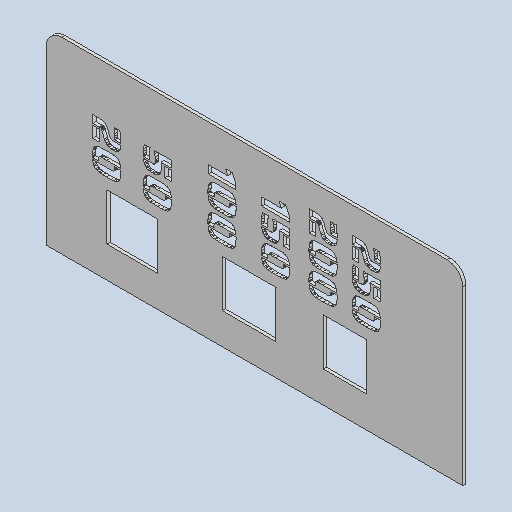
# Autodesk Inventor part: GBK-RK-0052 Cipolletti L
Saved by Autodesk Inventor 2026.2 (Build 302298000, 298)
## iProperties
Created: 2026-10-23
Part Number: GBK-RK-0052 Cipolletti L
Material: Generic
Description: Шкала расхода водослива, левая (трафарет, Saira Stencil)
Document SubType Name: Sheet Metal
Designer: admin
Density: 1 g/cm^3
Sheet Metal Rule: Default_mm
Appearance: Default
Flat Pattern Width: 12 cm
Flat Pattern Length: 26.6044 cm
Flat Pattern Area: 319.253 cm^2
Sheet Metal Width: 120,000 mm
Sheet Metal Length: 266,044 mm
Sheet Metal Area: 31925,333 mm^2
Author: admin
Autodesk Inventor part; units mm, degrees
(part 1 of 2)
ref_plane "YZ Plane" through (0, 0, 0) normal (1, 0, 0) x (0, 1, 0)
ref_plane "XZ Plane" through (0, 0, 0) normal (0, 1, 0) x (-1, 0, 0)
ref_plane "XY Plane" through (0, 0, 0) normal (0, 0, 1) x (1, 0, 0)
sketch "Sketch1" plane through (0, 0, 0) normal (0, 0, 1) x (1, 0, 0)
  line L0 (0, 0) -> (266.0444, 0)
  line L1 (266.0444, 0) -> (266.0444, 120)
  line L2 (266.0444, 120) -> (0, 120)
  line L3 (0, 120) -> (0, 0)
extrude "Plate1" add sketch "Sketch1" along normal blind 2
sketch "Sketch3" plane through (0, 0, 0) normal (0, 0, -1) x (-1, 0, 0)
  line L0 (-38.8424, 20) -> (-71.2409, 20)
  line L1 (-71.2409, 20) -> (-71.2409, 50)
  line L2 (-71.2409, 50) -> (-38.8424, 50)
  line L3 (-38.8424, 50) -> (-38.8424, 20)
  line L4 (-112.4742, 20) -> (-146.7233, 20)
  line L5 (-146.7233, 20) -> (-146.7233, 50)
  line L6 (-146.7233, 50) -> (-112.4742, 50)
  line L7 (-112.4742, 50) -> (-112.4742, 20)
  line L8 (-177.0426, 20) -> (-204.7056, 20)
  line L9 (-204.7056, 20) -> (-204.7056, 50)
  line L10 (-204.7056, 50) -> (-177.0426, 50)
  line L11 (-177.0426, 50) -> (-177.0426, 20)
  line L12 (-46.9971, 86.8148) -> (-47.3068, 85.1782)
  line L13 (-47.3068, 85.1782) -> (-47.6264, 81.8282)
  line L14 (-47.6264, 81.8282) -> (-47.6363, 80.1152)
  line L15 (-47.6363, 80.1152) -> (-43.6492, 80.1152)
  line L16 (-43.6492, 80.1152) -> (-43.7063, 80.8612)
  line L17 (-43.7063, 80.8612) -> (-43.7252, 82.1328)
  line L18 (-43.7252, 82.1328) -> (-43.6743, 83.5339)
  line L19 (-43.6743, 83.5339) -> (-43.5214, 85.2288)
  line L20 (-43.5214, 85.2288) -> (-43.3176, 86.8148)
  line L21 (-43.3176, 86.8148) -> (-46.9971, 86.8148)
  line L22 (-32.4233, 87.1705) -> (-33.9254, 87.1454)
  line L23 (-33.9254, 87.1454) -> (-35.1079, 87.0705)
  line L24 (-35.1079, 87.0705) -> (-35.6017, 87.0043)
  line L25 (-35.6017, 87.0043) -> (-36.4848, 86.7867)
  line L26 (-36.4848, 86.7867) -> (-36.8737, 86.6351)
  line L27 (-36.8737, 86.6351) -> (-37.2557, 86.4372)
  line L28 (-37.2557, 86.4372) -> (-37.9388, 85.9317)
  line L29 (-37.9388, 85.9317) -> (-38.24, 85.6243)
  line L30 (-38.24, 85.6243) -> (-38.5205, 85.2689)
  line L31 (-38.5205, 85.2689) -> (-39.0401, 84.3802)
  line L32 (-39.0401, 84.3802) -> (-39.2786, 83.8466)
  line L33 (-39.2786, 83.8466) -> (-40.4773, 80.8543)
  line L34 (-40.4773, 80.8543) -> (-40.6989, 80.333)
  line L35 (-40.6989, 80.333) -> (-40.9007, 79.8874)
  line L36 (-40.9007, 79.8874) -> (-41.0894, 79.5399)
  line L37 (-41.0894, 79.5399) -> (-41.2722, 79.3203)
  line L38 (-41.2722, 79.3203) -> (-41.467, 79.1753)
  line L39 (-41.467, 79.1753) -> (-41.6917, 79.0924)
  line L40 (-41.6917, 79.0924) -> (-41.9894, 79.0536)
  line L41 (-41.9894, 79.0536) -> (-42.3949, 79.0405)
  line L42 (-42.3949, 79.0405) -> (-47.6123, 79.0405)
  line L43 (-47.6123, 79.0405) -> (-47.5003, 77.8999)
  line L44 (-47.5003, 77.8999) -> (-47.3167, 76.9312)
  line L45 (-47.3167, 76.9312) -> (-47.1917, 76.5049)
  line L46 (-47.1917, 76.5049) -> (-46.8401, 75.7438)
  line L47 (-46.8401, 75.7438) -> (-46.6136, 75.4091)
  line L48 (-46.6136, 75.4091) -> (-46.2996, 75.0616)
  line L49 (-46.2996, 75.0616) -> (-45.5137, 74.5058)
  line L50 (-45.5137, 74.5058) -> (-44.5168, 74.1353)
  line L51 (-44.5168, 74.1353) -> (-43.3092, 73.9502)
  line L52 (-43.3092, 73.9502) -> (-42.6265, 73.9269)
  line L53 (-42.6265, 73.9269) -> (-41.4782, 73.978)
  line L54 (-41.4782, 73.978) -> (-40.0487, 74.2468)
  line L55 (-40.0487, 74.2468) -> (-39.2911, 74.5538)
  line L56 (-39.2911, 74.5538) -> (-38.971, 74.7459)
  line L57 (-38.971, 74.7459) -> (-38.6913, 74.9527)
  line L58 (-38.6913, 74.9527) -> (-38.1799, 75.4577)
  line L59 (-38.1799, 75.4577) -> (-37.5328, 76.4426)
  line L60 (-37.5328, 76.4426) -> (-37.1813, 77.2508)
  line L61 (-37.1813, 77.2508) -> (-35.775, 80.8822)
  line L62 (-35.775, 80.8822) -> (-35.6011, 81.3008)
  line L63 (-35.6011, 81.3008) -> (-35.4396, 81.6372)
  line L64 (-35.4396, 81.6372) -> (-35.2877, 81.8881)
  line L65 (-35.2877, 81.8881) -> (-35.1358, 82.0568)
  line L66 (-35.1358, 82.0568) -> (-34.955, 82.1596)
  line L67 (-34.955, 82.1596) -> (-34.7244, 82.2125)
  line L68 (-34.7244, 82.2125) -> (-34.3859, 82.2307)
  line L69 (-34.3859, 82.2307) -> (-33.8814, 82.2366)
  line L70 (-33.8814, 82.2366) -> (-29.8424, 82.2366)
  line L71 (-29.8424, 82.2366) -> (-29.8424, 87.1705)
  line L72 (-29.8424, 87.1705) -> (-32.4233, 87.1705)
  line L73 (-33.8295, 81.1619) -> (-33.8295, 73.9269)
  line L74 (-33.8295, 73.9269) -> (-29.8424, 73.9269)
  line L75 (-29.8424, 73.9269) -> (-29.8424, 81.1619)
  line L76 (-29.8424, 81.1619) -> (-33.8295, 81.1619)
  line L77 (-38.6394, 62.2136) -> (-40.4783, 62.2205)
  line L78 (-40.4783, 62.2205) -> (-41.5519, 62.2415)
  line L79 (-41.5519, 62.2415) -> (-42.4667, 62.3184)
  line L80 (-42.4667, 62.3184) -> (-43.0619, 62.4453)
  line L81 (-43.0619, 62.4453) -> (-43.2596, 62.547)
  line L82 (-43.2596, 62.547) -> (-43.5332, 62.8226)
  line L83 (-43.5332, 62.8226) -> (-43.6094, 62.9965)
  line L84 (-43.6094, 62.9965) -> (-43.6963, 63.49)
  line L85 (-43.6963, 63.49) -> (-43.7252, 64.235)
  line L86 (-43.7252, 64.235) -> (-43.7121, 64.6636)
  line L87 (-43.7121, 64.6636) -> (-43.6733, 65.1818)
  line L88 (-43.6733, 65.1818) -> (-47.6123, 65.1818)
  line L89 (-47.6123, 65.1818) -> (-47.6302, 64.989)
  line L90 (-47.6302, 64.989) -> (-47.6363, 64.7224)
  line L91 (-47.6363, 64.7224) -> (-47.6363, 64.235)
  line L92 (-47.6363, 64.235) -> (-47.6082, 62.9694)
  line L93 (-47.6082, 62.9694) -> (-47.3845, 60.8979)
  line L94 (-47.3845, 60.8979) -> (-47.1889, 60.0922)
  line L95 (-47.1889, 60.0922) -> (-46.9291, 59.4113)
  line L96 (-46.9291, 59.4113) -> (-46.194, 58.3385)
  line L97 (-46.194, 58.3385) -> (-45.7187, 57.9468)
  line L98 (-45.7187, 57.9468) -> (-45.2102, 57.6576)
  line L99 (-45.2102, 57.6576) -> (-43.9719, 57.2621)
  line L100 (-43.9719, 57.2621) -> (-43.2417, 57.1557)
  line L101 (-43.2417, 57.1557) -> (-41.3241, 57.0389)
  line L102 (-41.3241, 57.0389) -> (-38.6394, 57)
  line L103 (-38.6394, 57) -> (-36.2084, 57.0289)
  line L104 (-36.2084, 57.0289) -> (-34.4447, 57.1158)
  line L105 (-34.4447, 57.1158) -> (-33.7579, 57.1938)
  line L106 (-33.7579, 57.1938) -> (-32.5555, 57.4814)
  line L107 (-32.5555, 57.4814) -> (-32.0398, 57.6911)
  line L108 (-32.0398, 57.6911) -> (-31.5368, 57.9813)
  line L109 (-31.5368, 57.9813) -> (-30.7258, 58.7683)
  line L110 (-30.7258, 58.7683) -> (-30.4177, 59.2651)
  line L111 (-30.4177, 59.2651) -> (-30.1671, 59.8465)
  line L112 (-30.1671, 59.8465) -> (-29.8156, 61.3205)
  line L113 (-29.8156, 61.3205) -> (-29.7146, 62.2136)
  line L114 (-29.7146, 62.2136) -> (-38.6394, 62.2136)
  line L115 (-29.6386, 64.235) -> (-29.6665, 65.4909)
  line L116 (-29.6665, 65.4909) -> (-29.8905, 67.5563)
  line L117 (-29.8905, 67.5563) -> (-30.0861, 68.3658)
  line L118 (-30.0861, 68.3658) -> (-30.3474, 69.0521)
  line L119 (-30.3474, 69.0521) -> (-31.0942, 70.1305)
  line L120 (-31.0942, 70.1305) -> (-31.5803, 70.5233)
  line L121 (-31.5803, 70.5233) -> (-32.0886, 70.8124)
  line L122 (-32.0886, 70.8124) -> (-33.3151, 71.21)
  line L123 (-33.3151, 71.21) -> (-34.0333, 71.3182)
  line L124 (-34.0333, 71.3182) -> (-35.9399, 71.432)
  line L125 (-35.9399, 71.432) -> (-38.6394, 71.4701)
  line L126 (-38.6394, 71.4701) -> (-41.0674, 71.4419)
  line L127 (-41.0674, 71.4419) -> (-42.8303, 71.3581)
  line L128 (-42.8303, 71.3581) -> (-43.5183, 71.2786)
  line L129 (-43.5183, 71.2786) -> (-44.7208, 70.9889)
  line L130 (-44.7208, 70.9889) -> (-45.2352, 70.7789)
  line L131 (-45.2352, 70.7789) -> (-45.7397, 70.489)
  line L132 (-45.7397, 70.489) -> (-46.5507, 69.7038)
  line L133 (-46.5507, 69.7038) -> (-46.8573, 69.2088)
  line L134 (-46.8573, 69.2088) -> (-47.1078, 68.6259)
  line L135 (-47.1078, 68.6259) -> (-47.4594, 67.1495)
  line L136 (-47.4594, 67.1495) -> (-47.5604, 66.2564)
  line L137 (-47.5604, 66.2564) -> (-38.6394, 66.2564)
  line L138 (-38.6394, 66.2564) -> (-36.8156, 66.2495)
  line L139 (-36.8156, 66.2495) -> (-35.7471, 66.2286)
  line L140 (-35.7471, 66.2286) -> (-34.8523, 66.1455)
  line L141 (-34.8523, 66.1455) -> (-34.213, 66.0008)
  line L142 (-34.213, 66.0008) -> (-34.0169, 65.8998)
  line L143 (-34.0169, 65.8998) -> (-33.7434, 65.6323)
  line L144 (-33.7434, 65.6323) -> (-33.6656, 65.4654)
  line L145 (-33.6656, 65.4654) -> (-33.5787, 64.978)
  line L146 (-33.5787, 64.978) -> (-33.5498, 64.235)
  line L147 (-33.5498, 64.235) -> (-33.5498, 63.7237)
  line L148 (-33.5498, 63.7237) -> (-33.5628, 63.5247)
  line L149 (-33.5628, 63.5247) -> (-33.6017, 63.2882)
  line L150 (-33.6017, 63.2882) -> (-29.6627, 63.2882)
  line L151 (-29.6627, 63.2882) -> (-29.6448, 63.481)
  line L152 (-29.6448, 63.481) -> (-29.6386, 63.7477)
  line L153 (-29.6386, 63.7477) -> (-29.6386, 64.235)
  line L154 (-67.7381, 79.0886) -> (-68.3213, 79.1116)
  line L155 (-68.3213, 79.1116) -> (-68.7449, 79.1804)
  line L156 (-68.7449, 79.1804) -> (-69.0505, 79.3164)
  line L157 (-69.0505, 79.3164) -> (-69.2721, 79.5481)
  line L158 (-69.2721, 79.5481) -> (-69.423, 79.8825)
  line L159 (-69.423, 79.8825) -> (-69.5158, 80.3189)
  line L160 (-69.5158, 80.3189) -> (-69.5639, 80.9114)
  line L161 (-69.5639, 80.9114) -> (-69.5797, 81.7214)
  line L162 (-69.5797, 81.7214) -> (-69.5409, 83.461)
  line L163 (-69.5409, 83.461) -> (-69.424, 85.3009)
  line L164 (-69.424, 85.3009) -> (-69.3419, 86.2927)
  line L165 (-69.3419, 86.2927) -> (-69.2962, 86.8629)
  line L166 (-69.2962, 86.8629) -> (-79.831, 86.8629)
  line L167 (-79.831, 86.8629) -> (-79.831, 82.5403)
  line L168 (-79.831, 82.5403) -> (-73.339, 82.5403)
  line L169 (-73.339, 82.5403) -> (-73.415, 81.6973)
  line L170 (-73.415, 81.6973) -> (-73.472, 80.1883)
  line L171 (-73.472, 80.1883) -> (-73.4909, 79.1924)
  line L172 (-73.4909, 79.1924) -> (-73.4681, 78.4594)
  line L173 (-73.4681, 78.4594) -> (-73.2858, 77.1615)
  line L174 (-73.2858, 77.1615) -> (-72.9212, 76.0879)
  line L175 (-72.9212, 76.0879) -> (-72.3746, 75.2386)
  line L176 (-72.3746, 75.2386) -> (-72.0327, 74.8977)
  line L177 (-72.0327, 74.8977) -> (-71.6827, 74.6372)
  line L178 (-71.6827, 74.6372) -> (-70.8717, 74.2416)
  line L179 (-70.8717, 74.2416) -> (-70.4107, 74.1066)
  line L180 (-70.4107, 74.1066) -> (-69.908, 74.0054)
  line L181 (-69.908, 74.0054) -> (-68.7636, 73.8896)
  line L182 (-68.7636, 73.8896) -> (-68.1216, 73.875)
  line L183 (-68.1216, 73.875) -> (-67.397, 73.8896)
  line L184 (-67.397, 73.8896) -> (-66.1306, 74.0054)
  line L185 (-66.1306, 74.0054) -> (-65.5888, 74.1066)
  line L186 (-65.5888, 74.1066) -> (-65.0966, 74.2416)
  line L187 (-65.0966, 74.2416) -> (-64.2278, 74.6372)
  line L188 (-64.2278, 74.6372) -> (-63.8509, 74.8977)
  line L189 (-63.8509, 74.8977) -> (-63.5116, 75.2074)
  line L190 (-63.5116, 75.2074) -> (-62.9422, 76.0064)
  line L191 (-62.9422, 76.0064) -> (-62.7124, 76.4957)
  line L192 (-62.7124, 76.4957) -> (-62.5191, 77.046)
  line L193 (-62.5191, 77.046) -> (-62.2314, 78.3423)
  line L194 (-62.2314, 78.3423) -> (-62.1371, 79.0886)
  line L195 (-62.1371, 79.0886) -> (-67.7381, 79.0886)
  line L196 (-79.831, 81.4657) -> (-79.831, 75.1774)
  line L197 (-79.831, 75.1774) -> (-75.868, 75.1774)
  line L198 (-75.868, 75.1774) -> (-75.868, 81.4657)
  line L199 (-75.868, 81.4657) -> (-79.831, 81.4657)
  line L200 (-62.0371, 81.3897) -> (-62.0821, 82.9417)
  line L201 (-62.0821, 82.9417) -> (-62.2169, 84.4738)
  line L202 (-62.2169, 84.4738) -> (-62.4127, 85.8811)
  line L203 (-62.4127, 85.8811) -> (-62.6485, 87.0666)
  line L204 (-62.6485, 87.0666) -> (-66.3078, 87.0666)
  line L205 (-66.3078, 87.0666) -> (-66.161, 85.6445)
  line L206 (-66.161, 85.6445) -> (-65.9933, 83.0877)
  line L207 (-65.9933, 83.0877) -> (-65.9723, 81.953)
  line L208 (-65.9723, 81.953) -> (-65.9854, 80.9042)
  line L209 (-65.9854, 80.9042) -> (-66.0242, 80.1632)
  line L210 (-66.0242, 80.1632) -> (-62.0611, 80.1632)
  line L211 (-62.0611, 80.1632) -> (-62.0433, 80.6736)
  line L212 (-62.0433, 80.6736) -> (-62.0371, 81.3897)
  line L213 (-71.0379, 62.2136) -> (-72.8767, 62.2205)
  line L214 (-72.8767, 62.2205) -> (-73.9504, 62.2415)
  line L215 (-73.9504, 62.2415) -> (-74.8652, 62.3184)
  line L216 (-74.8652, 62.3184) -> (-75.4604, 62.4453)
  line L217 (-75.4604, 62.4453) -> (-75.6581, 62.5473)
  line L218 (-75.6581, 62.5473) -> (-75.9316, 62.8229)
  line L219 (-75.9316, 62.8229) -> (-76.0078, 62.9965)
  line L220 (-76.0078, 62.9965) -> (-76.0948, 63.49)
  line L221 (-76.0948, 63.49) -> (-76.1236, 64.235)
  line L222 (-76.1236, 64.235) -> (-76.1106, 64.6636)
  line L223 (-76.1106, 64.6636) -> (-76.0717, 65.1818)
  line L224 (-76.0717, 65.1818) -> (-80.0108, 65.1818)
  line L225 (-80.0108, 65.1818) -> (-80.0287, 64.989)
  line L226 (-80.0287, 64.989) -> (-80.0348, 64.7224)
  line L227 (-80.0348, 64.7224) -> (-80.0348, 64.235)
  line L228 (-80.0348, 64.235) -> (-80.0067, 62.9694)
  line L229 (-80.0067, 62.9694) -> (-79.783, 60.8979)
  line L230 (-79.783, 60.8979) -> (-79.5874, 60.0922)
  line L231 (-79.5874, 60.0922) -> (-79.3276, 59.4113)
  line L232 (-79.3276, 59.4113) -> (-78.5925, 58.3387)
  line L233 (-78.5925, 58.3387) -> (-78.1172, 57.9468)
  line L234 (-78.1172, 57.9468) -> (-77.6086, 57.6579)
  line L235 (-77.6086, 57.6579) -> (-76.3704, 57.2623)
  line L236 (-76.3704, 57.2623) -> (-75.6402, 57.156)
  line L237 (-75.6402, 57.156) -> (-73.7225, 57.0391)
  line L238 (-73.7225, 57.0391) -> (-71.0379, 57)
  line L239 (-71.0379, 57) -> (-68.6069, 57.0291)
  line L240 (-68.6069, 57.0291) -> (-66.8432, 57.1158)
  line L241 (-66.8432, 57.1158) -> (-66.1564, 57.1938)
  line L242 (-66.1564, 57.1938) -> (-64.9539, 57.4814)
  line L243 (-64.9539, 57.4814) -> (-64.4382, 57.6911)
  line L244 (-64.4382, 57.6911) -> (-63.9353, 57.9813)
  line L245 (-63.9353, 57.9813) -> (-63.1243, 58.7683)
  line L246 (-63.1243, 58.7683) -> (-62.8162, 59.2653)
  line L247 (-62.8162, 59.2653) -> (-62.5656, 59.8465)
  line L248 (-62.5656, 59.8465) -> (-62.214, 61.3208)
  line L249 (-62.214, 61.3208) -> (-62.1131, 62.2136)
  line L250 (-62.1131, 62.2136) -> (-71.0379, 62.2136)
  line L251 (-62.0371, 64.235) -> (-62.065, 65.4909)
  line L252 (-62.065, 65.4909) -> (-62.289, 67.5563)
  line L253 (-62.289, 67.5563) -> (-62.4846, 68.3658)
  line L254 (-62.4846, 68.3658) -> (-62.7459, 69.0521)
  line L255 (-62.7459, 69.0521) -> (-63.4927, 70.1308)
  line L256 (-63.4927, 70.1308) -> (-63.9788, 70.5233)
  line L257 (-63.9788, 70.5233) -> (-64.4871, 70.8127)
  line L258 (-64.4871, 70.8127) -> (-65.7136, 71.21)
  line L259 (-65.7136, 71.21) -> (-66.4318, 71.3182)
  line L260 (-66.4318, 71.3182) -> (-68.3384, 71.4322)
  line L261 (-68.3384, 71.4322) -> (-71.0379, 71.4701)
  line L262 (-71.0379, 71.4701) -> (-73.4658, 71.4422)
  line L263 (-73.4658, 71.4422) -> (-75.2288, 71.3581)
  line L264 (-75.2288, 71.3581) -> (-75.9168, 71.2786)
  line L265 (-75.9168, 71.2786) -> (-77.1193, 70.9889)
  line L266 (-77.1193, 70.9889) -> (-77.6337, 70.7789)
  line L267 (-77.6337, 70.7789) -> (-78.1382, 70.489)
  line L268 (-78.1382, 70.489) -> (-78.9492, 69.7041)
  line L269 (-78.9492, 69.7041) -> (-79.2558, 69.2088)
  line L270 (-79.2558, 69.2088) -> (-79.5063, 68.6259)
  line L271 (-79.5063, 68.6259) -> (-79.8579, 67.1498)
  line L272 (-79.8579, 67.1498) -> (-79.9589, 66.2564)
  line L273 (-79.9589, 66.2564) -> (-71.0379, 66.2564)
  line L274 (-71.0379, 66.2564) -> (-69.2141, 66.2495)
  line L275 (-69.2141, 66.2495) -> (-68.1456, 66.2286)
  line L276 (-68.1456, 66.2286) -> (-67.2507, 66.1457)
  line L277 (-67.2507, 66.1457) -> (-66.6115, 66.0008)
  line L278 (-66.6115, 66.0008) -> (-66.4154, 65.9)
  line L279 (-66.4154, 65.9) -> (-66.1418, 65.6323)
  line L280 (-66.1418, 65.6323) -> (-66.0641, 65.4656)
  line L281 (-66.0641, 65.4656) -> (-65.9772, 64.978)
  line L282 (-65.9772, 64.978) -> (-65.9483, 64.235)
  line L283 (-65.9483, 64.235) -> (-65.9483, 63.7237)
  line L284 (-65.9483, 63.7237) -> (-65.9613, 63.525)
  line L285 (-65.9613, 63.525) -> (-66.0002, 63.2882)
  line L286 (-66.0002, 63.2882) -> (-62.0611, 63.2882)
  line L287 (-62.0611, 63.2882) -> (-62.0433, 63.481)
  line L288 (-62.0433, 63.481) -> (-62.0371, 63.7477)
  line L289 (-62.0371, 63.7477) -> (-62.0371, 64.235)
  line L290 (-115.9267, 96.3231) -> (-114.7002, 99.571)
  line L291 (-114.7002, 99.571) -> (-118.6873, 99.571)
  line L292 (-118.6873, 99.571) -> (-121.0644, 94.6093)
  line L293 (-121.0644, 94.6093) -> (-121.0644, 91.2095)
  line L294 (-121.0644, 91.2095) -> (-103.4742, 91.2095)
  line L295 (-103.4742, 91.2095) -> (-103.4742, 96.3231)
  line L296 (-103.4742, 96.3231) -> (-115.9267, 96.3231)
  line L297 (-112.2712, 79.0886) -> (-114.1101, 79.0955)
  line L298 (-114.1101, 79.0955) -> (-115.1837, 79.1165)
  line L299 (-115.1837, 79.1165) -> (-116.0985, 79.1934)
  line L300 (-116.0985, 79.1934) -> (-116.6938, 79.3203)
  line L301 (-116.6938, 79.3203) -> (-116.8914, 79.422)
  line L302 (-116.8914, 79.422) -> (-117.165, 79.6976)
  line L303 (-117.165, 79.6976) -> (-117.2412, 79.8715)
  line L304 (-117.2412, 79.8715) -> (-117.3281, 80.365)
  line L305 (-117.3281, 80.365) -> (-117.357, 81.11)
  line L306 (-117.357, 81.11) -> (-117.344, 81.5386)
  line L307 (-117.344, 81.5386) -> (-117.3051, 82.0568)
  line L308 (-117.3051, 82.0568) -> (-121.2441, 82.0568)
  line L309 (-121.2441, 82.0568) -> (-121.262, 81.864)
  line L310 (-121.262, 81.864) -> (-121.2682, 81.5974)
  line L311 (-121.2682, 81.5974) -> (-121.2682, 81.11)
  line L312 (-121.2682, 81.11) -> (-121.24, 79.8444)
  line L313 (-121.24, 79.8444) -> (-121.0163, 77.7729)
  line L314 (-121.0163, 77.7729) -> (-120.8207, 76.9672)
  line L315 (-120.8207, 76.9672) -> (-120.5609, 76.2863)
  line L316 (-120.5609, 76.2863) -> (-119.8259, 75.2135)
  line L317 (-119.8259, 75.2135) -> (-119.3505, 74.8218)
  line L318 (-119.3505, 74.8218) -> (-118.842, 74.5326)
  line L319 (-118.842, 74.5326) -> (-117.6037, 74.1371)
  line L320 (-117.6037, 74.1371) -> (-116.8735, 74.0307)
  line L321 (-116.8735, 74.0307) -> (-114.9559, 73.9139)
  line L322 (-114.9559, 73.9139) -> (-112.2712, 73.875)
  line L323 (-112.2712, 73.875) -> (-109.8402, 73.9039)
  line L324 (-109.8402, 73.9039) -> (-108.0765, 73.9908)
  line L325 (-108.0765, 73.9908) -> (-107.3898, 74.0688)
  line L326 (-107.3898, 74.0688) -> (-106.1873, 74.3564)
  line L327 (-106.1873, 74.3564) -> (-105.6716, 74.5661)
  line L328 (-105.6716, 74.5661) -> (-105.1686, 74.8563)
  line L329 (-105.1686, 74.8563) -> (-104.3576, 75.6433)
  line L330 (-104.3576, 75.6433) -> (-104.0495, 76.1401)
  line L331 (-104.0495, 76.1401) -> (-103.799, 76.7215)
  line L332 (-103.799, 76.7215) -> (-103.4474, 78.1955)
  line L333 (-103.4474, 78.1955) -> (-103.3464, 79.0886)
  line L334 (-103.3464, 79.0886) -> (-112.2712, 79.0886)
  line L335 (-103.2705, 81.11) -> (-103.2983, 82.3659)
  line L336 (-103.2983, 82.3659) -> (-103.5223, 84.4313)
  line L337 (-103.5223, 84.4313) -> (-103.7179, 85.2408)
  line L338 (-103.7179, 85.2408) -> (-103.9792, 85.9271)
  line L339 (-103.9792, 85.9271) -> (-104.7261, 87.0055)
  line L340 (-104.7261, 87.0055) -> (-105.2121, 87.3983)
  line L341 (-105.2121, 87.3983) -> (-105.7204, 87.6874)
  line L342 (-105.7204, 87.6874) -> (-106.9469, 88.085)
  line L343 (-106.9469, 88.085) -> (-107.6651, 88.1932)
  line L344 (-107.6651, 88.1932) -> (-109.5717, 88.307)
  line L345 (-109.5717, 88.307) -> (-112.2712, 88.3451)
  line L346 (-112.2712, 88.3451) -> (-114.6992, 88.3169)
  line L347 (-114.6992, 88.3169) -> (-116.4621, 88.2331)
  line L348 (-116.4621, 88.2331) -> (-117.1502, 88.1536)
  line L349 (-117.1502, 88.1536) -> (-118.3526, 87.8639)
  line L350 (-118.3526, 87.8639) -> (-118.8671, 87.6539)
  line L351 (-118.8671, 87.6539) -> (-119.3715, 87.364)
  line L352 (-119.3715, 87.364) -> (-120.1825, 86.5791)
  line L353 (-120.1825, 86.5791) -> (-120.4891, 86.0838)
  line L354 (-120.4891, 86.0838) -> (-120.7397, 85.5009)
  line L355 (-120.7397, 85.5009) -> (-121.0912, 84.0245)
  line L356 (-121.0912, 84.0245) -> (-121.1922, 83.1314)
  line L357 (-121.1922, 83.1314) -> (-112.2712, 83.1314)
  line L358 (-112.2712, 83.1314) -> (-110.4475, 83.1245)
  line L359 (-110.4475, 83.1245) -> (-109.379, 83.1036)
  line L360 (-109.379, 83.1036) -> (-108.4841, 83.0207)
  line L361 (-108.4841, 83.0207) -> (-107.8449, 82.8758)
  line L362 (-107.8449, 82.8758) -> (-107.6488, 82.775)
  line L363 (-107.6488, 82.775) -> (-107.3752, 82.5073)
  line L364 (-107.3752, 82.5073) -> (-107.2975, 82.3404)
  line L365 (-107.2975, 82.3404) -> (-107.2105, 81.853)
  line L366 (-107.2105, 81.853) -> (-107.1816, 81.11)
  line L367 (-107.1816, 81.11) -> (-107.1816, 80.5987)
  line L368 (-107.1816, 80.5987) -> (-107.1947, 80.4)
  line L369 (-107.1947, 80.4) -> (-107.2335, 80.1632)
  line L370 (-107.2335, 80.1632) -> (-103.2945, 80.1632)
  line L371 (-103.2945, 80.1632) -> (-103.2766, 80.356)
  line L372 (-103.2766, 80.356) -> (-103.2705, 80.6227)
  line L373 (-103.2705, 80.6227) -> (-103.2705, 81.11)
  line L374 (-112.2712, 62.2136) -> (-114.1101, 62.2205)
  line L375 (-114.1101, 62.2205) -> (-115.1837, 62.2415)
  line L376 (-115.1837, 62.2415) -> (-116.0985, 62.3184)
  line L377 (-116.0985, 62.3184) -> (-116.6938, 62.4453)
  line L378 (-116.6938, 62.4453) -> (-116.8914, 62.547)
  line L379 (-116.8914, 62.547) -> (-117.165, 62.8226)
  line L380 (-117.165, 62.8226) -> (-117.2412, 62.9965)
  line L381 (-117.2412, 62.9965) -> (-117.3281, 63.49)
  line L382 (-117.3281, 63.49) -> (-117.357, 64.235)
  line L383 (-117.357, 64.235) -> (-117.344, 64.6636)
  line L384 (-117.344, 64.6636) -> (-117.3051, 65.1818)
  line L385 (-117.3051, 65.1818) -> (-121.2441, 65.1818)
  line L386 (-121.2441, 65.1818) -> (-121.262, 64.989)
  line L387 (-121.262, 64.989) -> (-121.2682, 64.7224)
  line L388 (-121.2682, 64.7224) -> (-121.2682, 64.235)
  line L389 (-121.2682, 64.235) -> (-121.24, 62.9694)
  line L390 (-121.24, 62.9694) -> (-121.0163, 60.8979)
  line L391 (-121.0163, 60.8979) -> (-120.8207, 60.0922)
  line L392 (-120.8207, 60.0922) -> (-120.5609, 59.4113)
  line L393 (-120.5609, 59.4113) -> (-119.8259, 58.3385)
  line L394 (-119.8259, 58.3385) -> (-119.3505, 57.9468)
  line L395 (-119.3505, 57.9468) -> (-118.842, 57.6576)
  line L396 (-118.842, 57.6576) -> (-117.6037, 57.2621)
  line L397 (-117.6037, 57.2621) -> (-116.8735, 57.1557)
  line L398 (-116.8735, 57.1557) -> (-114.9559, 57.0389)
  line L399 (-114.9559, 57.0389) -> (-112.2712, 57)
  line L400 (-112.2712, 57) -> (-109.8402, 57.0289)
  line L401 (-109.8402, 57.0289) -> (-108.0765, 57.1158)
  line L402 (-108.0765, 57.1158) -> (-107.3898, 57.1938)
  line L403 (-107.3898, 57.1938) -> (-106.1873, 57.4814)
  line L404 (-106.1873, 57.4814) -> (-105.6716, 57.6911)
  line L405 (-105.6716, 57.6911) -> (-105.1686, 57.9813)
  line L406 (-105.1686, 57.9813) -> (-104.3576, 58.7683)
  line L407 (-104.3576, 58.7683) -> (-104.0495, 59.2651)
  line L408 (-104.0495, 59.2651) -> (-103.799, 59.8465)
  line L409 (-103.799, 59.8465) -> (-103.4474, 61.3205)
  line L410 (-103.4474, 61.3205) -> (-103.3464, 62.2136)
  line L411 (-103.3464, 62.2136) -> (-112.2712, 62.2136)
  line L412 (-103.2705, 64.235) -> (-103.2983, 65.4909)
  line L413 (-103.2983, 65.4909) -> (-103.5223, 67.5563)
  line L414 (-103.5223, 67.5563) -> (-103.7179, 68.3658)
  line L415 (-103.7179, 68.3658) -> (-103.9792, 69.0521)
  line L416 (-103.9792, 69.0521) -> (-104.7261, 70.1305)
  line L417 (-104.7261, 70.1305) -> (-105.2121, 70.5233)
  line L418 (-105.2121, 70.5233) -> (-105.7204, 70.8124)
  line L419 (-105.7204, 70.8124) -> (-106.9469, 71.21)
  line L420 (-106.9469, 71.21) -> (-107.6651, 71.3182)
  line L421 (-107.6651, 71.3182) -> (-109.5717, 71.432)
  line L422 (-109.5717, 71.432) -> (-112.2712, 71.4701)
  line L423 (-112.2712, 71.4701) -> (-114.6992, 71.4419)
  line L424 (-114.6992, 71.4419) -> (-116.4621, 71.3581)
  line L425 (-116.4621, 71.3581) -> (-117.1502, 71.2786)
  line L426 (-117.1502, 71.2786) -> (-118.3526, 70.9889)
  line L427 (-118.3526, 70.9889) -> (-118.8671, 70.7789)
  line L428 (-118.8671, 70.7789) -> (-119.3715, 70.489)
  line L429 (-119.3715, 70.489) -> (-120.1825, 69.7041)
  line L430 (-120.1825, 69.7041) -> (-120.4891, 69.2088)
  line L431 (-120.4891, 69.2088) -> (-120.7397, 68.6259)
  line L432 (-120.7397, 68.6259) -> (-121.0912, 67.1495)
  line L433 (-121.0912, 67.1495) -> (-121.1922, 66.2564)
  line L434 (-121.1922, 66.2564) -> (-112.2712, 66.2564)
  line L435 (-112.2712, 66.2564) -> (-110.4475, 66.2495)
  line L436 (-110.4475, 66.2495) -> (-109.379, 66.2286)
  line L437 (-109.379, 66.2286) -> (-108.4841, 66.1457)
  line L438 (-108.4841, 66.1457) -> (-107.8449, 66.0008)
  line L439 (-107.8449, 66.0008) -> (-107.6488, 65.9)
  line L440 (-107.6488, 65.9) -> (-107.3752, 65.6323)
  line L441 (-107.3752, 65.6323) -> (-107.2975, 65.4654)
  line L442 (-107.2975, 65.4654) -> (-107.2105, 64.978)
  line L443 (-107.2105, 64.978) -> (-107.1816, 64.235)
  line L444 (-107.1816, 64.235) -> (-107.1816, 63.7237)
  line L445 (-107.1816, 63.7237) -> (-107.1947, 63.525)
  line L446 (-107.1947, 63.525) -> (-107.2335, 63.2882)
  line L447 (-107.2335, 63.2882) -> (-103.2945, 63.2882)
  line L448 (-103.2945, 63.2882) -> (-103.2766, 63.481)
  line L449 (-103.2766, 63.481) -> (-103.2705, 63.7477)
  line L450 (-103.2705, 63.7477) -> (-103.2705, 64.235)
  line L451 (-150.1758, 95.5041) -> (-148.9493, 98.7521)
  line L452 (-148.9493, 98.7521) -> (-152.9364, 98.7521)
  line L453 (-152.9364, 98.7521) -> (-155.3134, 93.7903)
  line L454 (-155.3134, 93.7903) -> (-155.3134, 90.3905)
  line L455 (-155.3134, 90.3905) -> (-137.7233, 90.3905)
  line L456 (-137.7233, 90.3905) -> (-137.7233, 95.5041)
  line L457 (-137.7233, 95.5041) -> (-150.1758, 95.5041)
  line L458 (-143.2205, 79.0886) -> (-143.8037, 79.1116)
  line L459 (-143.8037, 79.1116) -> (-144.2273, 79.1804)
  line L460 (-144.2273, 79.1804) -> (-144.5329, 79.3162)
  line L461 (-144.5329, 79.3162) -> (-144.7546, 79.5481)
  line L462 (-144.7546, 79.5481) -> (-144.9054, 79.8825)
  line L463 (-144.9054, 79.8825) -> (-144.9982, 80.3189)
  line L464 (-144.9982, 80.3189) -> (-145.0463, 80.9114)
  line L465 (-145.0463, 80.9114) -> (-145.0621, 81.7214)
  line L466 (-145.0621, 81.7214) -> (-145.0233, 83.461)
  line L467 (-145.0233, 83.461) -> (-144.9064, 85.3009)
  line L468 (-144.9064, 85.3009) -> (-144.8244, 86.2927)
  line L469 (-144.8244, 86.2927) -> (-144.7786, 86.8629)
  line L470 (-144.7786, 86.8629) -> (-155.3134, 86.8629)
  line L471 (-155.3134, 86.8629) -> (-155.3134, 82.5403)
  line L472 (-155.3134, 82.5403) -> (-148.8214, 82.5403)
  line L473 (-148.8214, 82.5403) -> (-148.8974, 81.6973)
  line L474 (-148.8974, 81.6973) -> (-148.9544, 80.1883)
  line L475 (-148.9544, 80.1883) -> (-148.9733, 79.1924)
  line L476 (-148.9733, 79.1924) -> (-148.9506, 78.4594)
  line L477 (-148.9506, 78.4594) -> (-148.7682, 77.1615)
  line L478 (-148.7682, 77.1615) -> (-148.4036, 76.0879)
  line L479 (-148.4036, 76.0879) -> (-147.857, 75.2383)
  line L480 (-147.857, 75.2383) -> (-147.5152, 74.8977)
  line L481 (-147.5152, 74.8977) -> (-147.1651, 74.6372)
  line L482 (-147.1651, 74.6372) -> (-146.3541, 74.2416)
  line L483 (-146.3541, 74.2416) -> (-145.8931, 74.1066)
  line L484 (-145.8931, 74.1066) -> (-145.3904, 74.0054)
  line L485 (-145.3904, 74.0054) -> (-144.246, 73.8896)
  line L486 (-144.246, 73.8896) -> (-143.604, 73.875)
  line L487 (-143.604, 73.875) -> (-142.8794, 73.8896)
  line L488 (-142.8794, 73.8896) -> (-141.613, 74.0054)
  line L489 (-141.613, 74.0054) -> (-141.0712, 74.1066)
  line L490 (-141.0712, 74.1066) -> (-140.579, 74.2416)
  line L491 (-140.579, 74.2416) -> (-139.7102, 74.6372)
  line L492 (-139.7102, 74.6372) -> (-139.3333, 74.8977)
  line L493 (-139.3333, 74.8977) -> (-138.994, 75.2074)
  line L494 (-138.994, 75.2074) -> (-138.4246, 76.0064)
  line L495 (-138.4246, 76.0064) -> (-138.1948, 76.4957)
  line L496 (-138.1948, 76.4957) -> (-138.0015, 77.0457)
  line L497 (-138.0015, 77.0457) -> (-137.7138, 78.3423)
  line L498 (-137.7138, 78.3423) -> (-137.6195, 79.0886)
  line L499 (-137.6195, 79.0886) -> (-143.2205, 79.0886)
  line L500 (-155.3134, 81.4657) -> (-155.3134, 75.1774)
  line L501 (-155.3134, 75.1774) -> (-151.3504, 75.1774)
  line L502 (-151.3504, 75.1774) -> (-151.3504, 81.4657)
  line L503 (-151.3504, 81.4657) -> (-155.3134, 81.4657)
  line L504 (-137.5195, 81.3897) -> (-137.5645, 82.9417)
  line L505 (-137.5645, 82.9417) -> (-137.6993, 84.4738)
  line L506 (-137.6993, 84.4738) -> (-137.8951, 85.8811)
  line L507 (-137.8951, 85.8811) -> (-138.1309, 87.0666)
  line L508 (-138.1309, 87.0666) -> (-141.7902, 87.0666)
  line L509 (-141.7902, 87.0666) -> (-141.6434, 85.6443)
  line L510 (-141.6434, 85.6443) -> (-141.4757, 83.0875)
  line L511 (-141.4757, 83.0875) -> (-141.4547, 81.953)
  line L512 (-141.4547, 81.953) -> (-141.4678, 80.9042)
  line L513 (-141.4678, 80.9042) -> (-141.5066, 80.1632)
  line L514 (-141.5066, 80.1632) -> (-137.5436, 80.1632)
  line L515 (-137.5436, 80.1632) -> (-137.5257, 80.6736)
  line L516 (-137.5257, 80.6736) -> (-137.5195, 81.3897)
  line L517 (-146.5203, 62.2136) -> (-148.3592, 62.2205)
  line L518 (-148.3592, 62.2205) -> (-149.4328, 62.2415)
  line L519 (-149.4328, 62.2415) -> (-150.3476, 62.3184)
  line L520 (-150.3476, 62.3184) -> (-150.9428, 62.4453)
  line L521 (-150.9428, 62.4453) -> (-151.1405, 62.547)
  line L522 (-151.1405, 62.547) -> (-151.414, 62.8229)
  line L523 (-151.414, 62.8229) -> (-151.4902, 62.9965)
  line L524 (-151.4902, 62.9965) -> (-151.5772, 63.49)
  line L525 (-151.5772, 63.49) -> (-151.6061, 64.235)
  line L526 (-151.6061, 64.235) -> (-151.593, 64.6636)
  line L527 (-151.593, 64.6636) -> (-151.5542, 65.1818)
  line L528 (-151.5542, 65.1818) -> (-155.4932, 65.1818)
  line L529 (-155.4932, 65.1818) -> (-155.5111, 64.989)
  line L530 (-155.5111, 64.989) -> (-155.5172, 64.7224)
  line L531 (-155.5172, 64.7224) -> (-155.5172, 64.235)
  line L532 (-155.5172, 64.235) -> (-155.4891, 62.9694)
  line L533 (-155.4891, 62.9694) -> (-155.2654, 60.8979)
  line L534 (-155.2654, 60.8979) -> (-155.0698, 60.0922)
  line L535 (-155.0698, 60.0922) -> (-154.81, 59.4113)
  line L536 (-154.81, 59.4113) -> (-154.0749, 58.3385)
  line L537 (-154.0749, 58.3385) -> (-153.5996, 57.9468)
  line L538 (-153.5996, 57.9468) -> (-153.0911, 57.6576)
  line L539 (-153.0911, 57.6576) -> (-151.8528, 57.2623)
  line L540 (-151.8528, 57.2623) -> (-151.1226, 57.1557)
  line L541 (-151.1226, 57.1557) -> (-149.205, 57.0389)
  line L542 (-149.205, 57.0389) -> (-146.5203, 57)
  line L543 (-146.5203, 57) -> (-144.0893, 57.0289)
  line L544 (-144.0893, 57.0289) -> (-142.3256, 57.1158)
  line L545 (-142.3256, 57.1158) -> (-141.6388, 57.1938)
  line L546 (-141.6388, 57.1938) -> (-140.4363, 57.4814)
  line L547 (-140.4363, 57.4814) -> (-139.9206, 57.6911)
  line L548 (-139.9206, 57.6911) -> (-139.4177, 57.9813)
  line L549 (-139.4177, 57.9813) -> (-138.6067, 58.7683)
  line L550 (-138.6067, 58.7683) -> (-138.2986, 59.2651)
  line L551 (-138.2986, 59.2651) -> (-138.048, 59.8465)
  line L552 (-138.048, 59.8465) -> (-137.6965, 61.3208)
  line L553 (-137.6965, 61.3208) -> (-137.5955, 62.2136)
  line L554 (-137.5955, 62.2136) -> (-146.5203, 62.2136)
  line L555 (-137.5195, 64.235) -> (-137.5474, 65.4909)
  line L556 (-137.5474, 65.4909) -> (-137.7714, 67.5563)
  line L557 (-137.7714, 67.5563) -> (-137.967, 68.3658)
  line L558 (-137.967, 68.3658) -> (-138.2283, 69.0521)
  line L559 (-138.2283, 69.0521) -> (-138.9751, 70.1308)
  line L560 (-138.9751, 70.1308) -> (-139.4612, 70.5233)
  line L561 (-139.4612, 70.5233) -> (-139.9695, 70.8127)
  line L562 (-139.9695, 70.8127) -> (-141.196, 71.21)
  line L563 (-141.196, 71.21) -> (-141.9142, 71.3182)
  line L564 (-141.9142, 71.3182) -> (-143.8208, 71.432)
  line L565 (-143.8208, 71.432) -> (-146.5203, 71.4701)
  line L566 (-146.5203, 71.4701) -> (-148.9482, 71.4422)
  line L567 (-148.9482, 71.4422) -> (-150.7112, 71.3581)
  line L568 (-150.7112, 71.3581) -> (-151.3992, 71.2786)
  line L569 (-151.3992, 71.2786) -> (-152.6017, 70.9889)
  line L570 (-152.6017, 70.9889) -> (-153.1161, 70.7789)
  line L571 (-153.1161, 70.7789) -> (-153.6206, 70.489)
  line L572 (-153.6206, 70.489) -> (-154.4316, 69.7041)
  line L573 (-154.4316, 69.7041) -> (-154.7382, 69.2088)
  line L574 (-154.7382, 69.2088) -> (-154.9887, 68.6259)
  line L575 (-154.9887, 68.6259) -> (-155.3403, 67.1495)
  line L576 (-155.3403, 67.1495) -> (-155.4413, 66.2564)
  line L577 (-155.4413, 66.2564) -> (-146.5203, 66.2564)
  line L578 (-146.5203, 66.2564) -> (-144.6965, 66.2495)
  line L579 (-144.6965, 66.2495) -> (-143.628, 66.2286)
  line L580 (-143.628, 66.2286) -> (-142.7331, 66.1457)
  line L581 (-142.7331, 66.1457) -> (-142.0939, 66.0008)
  line L582 (-142.0939, 66.0008) -> (-141.8978, 65.9)
  line L583 (-141.8978, 65.9) -> (-141.6242, 65.6323)
  line L584 (-141.6242, 65.6323) -> (-141.5465, 65.4654)
  line L585 (-141.5465, 65.4654) -> (-141.4596, 64.978)
  line L586 (-141.4596, 64.978) -> (-141.4307, 64.235)
  line L587 (-141.4307, 64.235) -> (-141.4307, 63.7237)
  line L588 (-141.4307, 63.7237) -> (-141.4437, 63.525)
  line L589 (-141.4437, 63.525) -> (-141.4826, 63.2882)
  line L590 (-141.4826, 63.2882) -> (-137.5436, 63.2882)
  line L591 (-137.5436, 63.2882) -> (-137.5257, 63.481)
  line L592 (-137.5257, 63.481) -> (-137.5195, 63.7477)
  line L593 (-137.5195, 63.7477) -> (-137.5195, 64.235)
  line L594 (-185.1973, 103.6898) -> (-185.507, 102.0532)
  line L595 (-185.507, 102.0532) -> (-185.8266, 98.7032)
  line L596 (-185.8266, 98.7032) -> (-185.8366, 96.9902)
  line L597 (-185.8366, 96.9902) -> (-181.8494, 96.9902)
  line L598 (-181.8494, 96.9902) -> (-181.9065, 97.7362)
  line L599 (-181.9065, 97.7362) -> (-181.9254, 99.0078)
  line L600 (-181.9254, 99.0078) -> (-181.8745, 100.4089)
  line L601 (-181.8745, 100.4089) -> (-181.7216, 102.1038)
  line L602 (-181.7216, 102.1038) -> (-181.5178, 103.6898)
  line L603 (-181.5178, 103.6898) -> (-185.1973, 103.6898)
  line L604 (-170.6235, 104.0455) -> (-172.1256, 104.0204)
  line L605 (-172.1256, 104.0204) -> (-173.3081, 103.9455)
  line L606 (-173.3081, 103.9455) -> (-173.8019, 103.8793)
  line L607 (-173.8019, 103.8793) -> (-174.685, 103.6617)
  line L608 (-174.685, 103.6617) -> (-175.0739, 103.5101)
  line L609 (-175.0739, 103.5101) -> (-175.4559, 103.3122)
  line L610 (-175.4559, 103.3122) -> (-176.1391, 102.8067)
  line L611 (-176.1391, 102.8067) -> (-176.4402, 102.4993)
  line L612 (-176.4402, 102.4993) -> (-176.7207, 102.1439)
  line L613 (-176.7207, 102.1439) -> (-177.2403, 101.2552)
  line L614 (-177.2403, 101.2552) -> (-177.4788, 100.7216)
  line L615 (-177.4788, 100.7216) -> (-178.6775, 97.7293)
  line L616 (-178.6775, 97.7293) -> (-178.8991, 97.208)
  line L617 (-178.8991, 97.208) -> (-179.1009, 96.7624)
  line L618 (-179.1009, 96.7624) -> (-179.2896, 96.4149)
  line L619 (-179.2896, 96.4149) -> (-179.4724, 96.1953)
  line L620 (-179.4724, 96.1953) -> (-179.6672, 96.0503)
  line L621 (-179.6672, 96.0503) -> (-179.8919, 95.9674)
  line L622 (-179.8919, 95.9674) -> (-180.1896, 95.9286)
  line L623 (-180.1896, 95.9286) -> (-180.5951, 95.9155)
  line L624 (-180.5951, 95.9155) -> (-185.8125, 95.9155)
  line L625 (-185.8125, 95.9155) -> (-185.7005, 94.7749)
  line L626 (-185.7005, 94.7749) -> (-185.5169, 93.8062)
  line L627 (-185.5169, 93.8062) -> (-185.3919, 93.3799)
  line L628 (-185.3919, 93.3799) -> (-185.0404, 92.6188)
  line L629 (-185.0404, 92.6188) -> (-184.8138, 92.2841)
  line L630 (-184.8138, 92.2841) -> (-184.4998, 91.9366)
  line L631 (-184.4998, 91.9366) -> (-183.7139, 91.3808)
  line L632 (-183.7139, 91.3808) -> (-182.717, 91.0103)
  line L633 (-182.717, 91.0103) -> (-181.5094, 90.8252)
  line L634 (-181.5094, 90.8252) -> (-180.8267, 90.8019)
  line L635 (-180.8267, 90.8019) -> (-179.6785, 90.853)
  line L636 (-179.6785, 90.853) -> (-178.2489, 91.1218)
  line L637 (-178.2489, 91.1218) -> (-177.4914, 91.4288)
  line L638 (-177.4914, 91.4288) -> (-177.1712, 91.6209)
  line L639 (-177.1712, 91.6209) -> (-176.8915, 91.8277)
  line L640 (-176.8915, 91.8277) -> (-176.3802, 92.3327)
  line L641 (-176.3802, 92.3327) -> (-175.733, 93.3176)
  line L642 (-175.733, 93.3176) -> (-175.3815, 94.1258)
  line L643 (-175.3815, 94.1258) -> (-173.9752, 97.7572)
  line L644 (-173.9752, 97.7572) -> (-173.8014, 98.1758)
  line L645 (-173.8014, 98.1758) -> (-173.6398, 98.5122)
  line L646 (-173.6398, 98.5122) -> (-173.4879, 98.7631)
  line L647 (-173.4879, 98.7631) -> (-173.336, 98.9318)
  line L648 (-173.336, 98.9318) -> (-173.1552, 99.0346)
  line L649 (-173.1552, 99.0346) -> (-172.9246, 99.0875)
  line L650 (-172.9246, 99.0875) -> (-172.5861, 99.1057)
  line L651 (-172.5861, 99.1057) -> (-172.0816, 99.1116)
  line L652 (-172.0816, 99.1116) -> (-168.0426, 99.1116)
  line L653 (-168.0426, 99.1116) -> (-168.0426, 104.0455)
  line L654 (-168.0426, 104.0455) -> (-170.6235, 104.0455)
  line L655 (-172.0297, 98.0369) -> (-172.0297, 90.8019)
  line L656 (-172.0297, 90.8019) -> (-168.0426, 90.8019)
  line L657 (-168.0426, 90.8019) -> (-168.0426, 98.0369)
  line L658 (-168.0426, 98.0369) -> (-172.0297, 98.0369)
  line L659 (-176.8396, 79.0886) -> (-178.6785, 79.0955)
  line L660 (-178.6785, 79.0955) -> (-179.7521, 79.1165)
  line L661 (-179.7521, 79.1165) -> (-180.6669, 79.1934)
  line L662 (-180.6669, 79.1934) -> (-181.2621, 79.3203)
  line L663 (-181.2621, 79.3203) -> (-181.4598, 79.422)
  line L664 (-181.4598, 79.422) -> (-181.7334, 79.6976)
  line L665 (-181.7334, 79.6976) -> (-181.8096, 79.8715)
  line L666 (-181.8096, 79.8715) -> (-181.8965, 80.365)
  line L667 (-181.8965, 80.365) -> (-181.9254, 81.11)
  line L668 (-181.9254, 81.11) -> (-181.9123, 81.5386)
  line L669 (-181.9123, 81.5386) -> (-181.8735, 82.0568)
  line L670 (-181.8735, 82.0568) -> (-185.8125, 82.0568)
  line L671 (-185.8125, 82.0568) -> (-185.8304, 81.864)
  line L672 (-185.8304, 81.864) -> (-185.8366, 81.5974)
  line L673 (-185.8366, 81.5974) -> (-185.8366, 81.11)
  line L674 (-185.8366, 81.11) -> (-185.8084, 79.8444)
  line L675 (-185.8084, 79.8444) -> (-185.5847, 77.7729)
  line L676 (-185.5847, 77.7729) -> (-185.3891, 76.9672)
  line L677 (-185.3891, 76.9672) -> (-185.1293, 76.2863)
  line L678 (-185.1293, 76.2863) -> (-184.3943, 75.2135)
  line L679 (-184.3943, 75.2135) -> (-183.9189, 74.8218)
  line L680 (-183.9189, 74.8218) -> (-183.4104, 74.5326)
  line L681 (-183.4104, 74.5326) -> (-182.1721, 74.1371)
  line L682 (-182.1721, 74.1371) -> (-181.4419, 74.0307)
  line L683 (-181.4419, 74.0307) -> (-179.5243, 73.9139)
  line L684 (-179.5243, 73.9139) -> (-176.8396, 73.875)
  line L685 (-176.8396, 73.875) -> (-174.4086, 73.9039)
  line L686 (-174.4086, 73.9039) -> (-172.6449, 73.9908)
  line L687 (-172.6449, 73.9908) -> (-171.9581, 74.0688)
  line L688 (-171.9581, 74.0688) -> (-170.7557, 74.3564)
  line L689 (-170.7557, 74.3564) -> (-170.24, 74.5661)
  line L690 (-170.24, 74.5661) -> (-169.737, 74.8563)
  line L691 (-169.737, 74.8563) -> (-168.926, 75.6433)
  line L692 (-168.926, 75.6433) -> (-168.6179, 76.1401)
  line L693 (-168.6179, 76.1401) -> (-168.3673, 76.7215)
  line L694 (-168.3673, 76.7215) -> (-168.0158, 78.1955)
  line L695 (-168.0158, 78.1955) -> (-167.9148, 79.0886)
  line L696 (-167.9148, 79.0886) -> (-176.8396, 79.0886)
  line L697 (-167.8389, 81.11) -> (-167.8667, 82.3659)
  line L698 (-167.8667, 82.3659) -> (-168.0907, 84.4313)
  line L699 (-168.0907, 84.4313) -> (-168.2863, 85.2408)
  line L700 (-168.2863, 85.2408) -> (-168.5476, 85.9271)
  line L701 (-168.5476, 85.9271) -> (-169.2944, 87.0055)
  line L702 (-169.2944, 87.0055) -> (-169.7805, 87.3983)
  line L703 (-169.7805, 87.3983) -> (-170.2888, 87.6874)
  line L704 (-170.2888, 87.6874) -> (-171.5153, 88.085)
  line L705 (-171.5153, 88.085) -> (-172.2335, 88.1932)
  line L706 (-172.2335, 88.1932) -> (-174.1401, 88.307)
  line L707 (-174.1401, 88.307) -> (-176.8396, 88.3451)
  line L708 (-176.8396, 88.3451) -> (-179.2676, 88.3169)
  line L709 (-179.2676, 88.3169) -> (-181.0305, 88.2331)
  line L710 (-181.0305, 88.2331) -> (-181.7185, 88.1536)
  line L711 (-181.7185, 88.1536) -> (-182.921, 87.8639)
  line L712 (-182.921, 87.8639) -> (-183.4354, 87.6539)
  line L713 (-183.4354, 87.6539) -> (-183.9399, 87.364)
  line L714 (-183.9399, 87.364) -> (-184.7509, 86.5788)
  line L715 (-184.7509, 86.5788) -> (-185.0575, 86.0838)
  line L716 (-185.0575, 86.0838) -> (-185.3081, 85.5009)
  line L717 (-185.3081, 85.5009) -> (-185.6596, 84.0245)
  line L718 (-185.6596, 84.0245) -> (-185.7606, 83.1314)
  line L719 (-185.7606, 83.1314) -> (-176.8396, 83.1314)
  line L720 (-176.8396, 83.1314) -> (-175.0158, 83.1245)
  line L721 (-175.0158, 83.1245) -> (-173.9473, 83.1036)
  line L722 (-173.9473, 83.1036) -> (-173.0525, 83.0205)
  line L723 (-173.0525, 83.0205) -> (-172.4133, 82.8758)
  line L724 (-172.4133, 82.8758) -> (-172.2171, 82.7748)
  line L725 (-172.2171, 82.7748) -> (-171.9436, 82.5073)
  line L726 (-171.9436, 82.5073) -> (-171.8658, 82.3404)
  line L727 (-171.8658, 82.3404) -> (-171.7789, 81.853)
  line L728 (-171.7789, 81.853) -> (-171.75, 81.11)
  line L729 (-171.75, 81.11) -> (-171.75, 80.5987)
  line L730 (-171.75, 80.5987) -> (-171.7631, 80.3997)
  line L731 (-171.7631, 80.3997) -> (-171.8019, 80.1632)
  line L732 (-171.8019, 80.1632) -> (-167.8629, 80.1632)
  line L733 (-167.8629, 80.1632) -> (-167.845, 80.356)
  line L734 (-167.845, 80.356) -> (-167.8389, 80.6227)
  line L735 (-167.8389, 80.6227) -> (-167.8389, 81.11)
  line L736 (-176.8396, 62.2136) -> (-178.6785, 62.2205)
  line L737 (-178.6785, 62.2205) -> (-179.7521, 62.2415)
  line L738 (-179.7521, 62.2415) -> (-180.6669, 62.3184)
  line L739 (-180.6669, 62.3184) -> (-181.2621, 62.4453)
  line L740 (-181.2621, 62.4453) -> (-181.4598, 62.547)
  line L741 (-181.4598, 62.547) -> (-181.7334, 62.8226)
  line L742 (-181.7334, 62.8226) -> (-181.8096, 62.9965)
  line L743 (-181.8096, 62.9965) -> (-181.8965, 63.49)
  line L744 (-181.8965, 63.49) -> (-181.9254, 64.235)
  line L745 (-181.9254, 64.235) -> (-181.9123, 64.6636)
  line L746 (-181.9123, 64.6636) -> (-181.8735, 65.1818)
  line L747 (-181.8735, 65.1818) -> (-185.8125, 65.1818)
  line L748 (-185.8125, 65.1818) -> (-185.8304, 64.989)
  line L749 (-185.8304, 64.989) -> (-185.8366, 64.7224)
  line L750 (-185.8366, 64.7224) -> (-185.8366, 64.235)
  line L751 (-185.8366, 64.235) -> (-185.8084, 62.9694)
  line L752 (-185.8084, 62.9694) -> (-185.5847, 60.8979)
  line L753 (-185.5847, 60.8979) -> (-185.3891, 60.0922)
  line L754 (-185.3891, 60.0922) -> (-185.1293, 59.4113)
  line L755 (-185.1293, 59.4113) -> (-184.3943, 58.3385)
  line L756 (-184.3943, 58.3385) -> (-183.9189, 57.9468)
  line L757 (-183.9189, 57.9468) -> (-183.4104, 57.6576)
  line L758 (-183.4104, 57.6576) -> (-182.1721, 57.2621)
  line L759 (-182.1721, 57.2621) -> (-181.4419, 57.1557)
  line L760 (-181.4419, 57.1557) -> (-179.5243, 57.0389)
  line L761 (-179.5243, 57.0389) -> (-176.8396, 57)
  line L762 (-176.8396, 57) -> (-174.4086, 57.0289)
  line L763 (-174.4086, 57.0289) -> (-172.6449, 57.1158)
  line L764 (-172.6449, 57.1158) -> (-171.9581, 57.1938)
  line L765 (-171.9581, 57.1938) -> (-170.7557, 57.4814)
  line L766 (-170.7557, 57.4814) -> (-170.24, 57.6911)
  line L767 (-170.24, 57.6911) -> (-169.737, 57.9813)
  line L768 (-169.737, 57.9813) -> (-168.926, 58.7683)
  line L769 (-168.926, 58.7683) -> (-168.6179, 59.2651)
  line L770 (-168.6179, 59.2651) -> (-168.3673, 59.8465)
  line L771 (-168.3673, 59.8465) -> (-168.0158, 61.3205)
  line L772 (-168.0158, 61.3205) -> (-167.9148, 62.2136)
  line L773 (-167.9148, 62.2136) -> (-176.8396, 62.2136)
  line L774 (-167.8389, 64.235) -> (-167.8667, 65.4909)
  line L775 (-167.8667, 65.4909) -> (-168.0907, 67.5563)
  line L776 (-168.0907, 67.5563) -> (-168.2863, 68.3658)
  line L777 (-168.2863, 68.3658) -> (-168.5476, 69.0521)
  line L778 (-168.5476, 69.0521) -> (-169.2944, 70.1305)
  line L779 (-169.2944, 70.1305) -> (-169.7805, 70.5233)
  line L780 (-169.7805, 70.5233) -> (-170.2888, 70.8124)
  line L781 (-170.2888, 70.8124) -> (-171.5153, 71.21)
  line L782 (-171.5153, 71.21) -> (-172.2335, 71.3182)
  line L783 (-172.2335, 71.3182) -> (-174.1401, 71.432)
  line L784 (-174.1401, 71.432) -> (-176.8396, 71.4701)
  line L785 (-176.8396, 71.4701) -> (-179.2676, 71.4419)
  line L786 (-179.2676, 71.4419) -> (-181.0305, 71.3581)
  line L787 (-181.0305, 71.3581) -> (-181.7185, 71.2786)
  line L788 (-181.7185, 71.2786) -> (-182.921, 70.9889)
  line L789 (-182.921, 70.9889) -> (-183.4354, 70.7789)
  line L790 (-183.4354, 70.7789) -> (-183.9399, 70.489)
  line L791 (-183.9399, 70.489) -> (-184.7509, 69.7038)
  line L792 (-184.7509, 69.7038) -> (-185.0575, 69.2088)
  line L793 (-185.0575, 69.2088) -> (-185.3081, 68.6259)
  line L794 (-185.3081, 68.6259) -> (-185.6596, 67.1495)
  line L795 (-185.6596, 67.1495) -> (-185.7606, 66.2564)
  line L796 (-185.7606, 66.2564) -> (-176.8396, 66.2564)
  line L797 (-176.8396, 66.2564) -> (-175.0158, 66.2495)
  line L798 (-175.0158, 66.2495) -> (-173.9473, 66.2286)
  line L799 (-173.9473, 66.2286) -> (-173.0525, 66.1455)
  line L800 (-173.0525, 66.1455) -> (-172.4133, 66.0008)
  line L801 (-172.4133, 66.0008) -> (-172.2171, 65.8998)
  line L802 (-172.2171, 65.8998) -> (-171.9436, 65.6323)
  line L803 (-171.9436, 65.6323) -> (-171.8658, 65.4654)
  line L804 (-171.8658, 65.4654) -> (-171.7789, 64.978)
  line L805 (-171.7789, 64.978) -> (-171.75, 64.235)
  line L806 (-171.75, 64.235) -> (-171.75, 63.7237)
  line L807 (-171.75, 63.7237) -> (-171.7631, 63.5247)
  line L808 (-171.7631, 63.5247) -> (-171.8019, 63.2882)
  line L809 (-171.8019, 63.2882) -> (-167.8629, 63.2882)
  line L810 (-167.8629, 63.2882) -> (-167.845, 63.481)
  line L811 (-167.845, 63.481) -> (-167.8389, 63.7477)
  line L812 (-167.8389, 63.7477) -> (-167.8389, 64.235)
  line L813 (-212.8603, 102.8709) -> (-213.17, 101.2342)
  line L814 (-213.17, 101.2342) -> (-213.4896, 97.8843)
  line L815 (-213.4896, 97.8843) -> (-213.4995, 96.1712)
  line L816 (-213.4995, 96.1712) -> (-209.5124, 96.1712)
  line L817 (-209.5124, 96.1712) -> (-209.5694, 96.9173)
  line L818 (-209.5694, 96.9173) -> (-209.5884, 98.1888)
  line L819 (-209.5884, 98.1888) -> (-209.5375, 99.5899)
  line L820 (-209.5375, 99.5899) -> (-209.3846, 101.2849)
  line L821 (-209.3846, 101.2849) -> (-209.1808, 102.8709)
  line L822 (-209.1808, 102.8709) -> (-212.8603, 102.8709)
  line L823 (-198.2865, 103.2265) -> (-199.7886, 103.2014)
  line L824 (-199.7886, 103.2014) -> (-200.9711, 103.1265)
  line L825 (-200.9711, 103.1265) -> (-201.4648, 103.0603)
  line L826 (-201.4648, 103.0603) -> (-202.348, 102.8427)
  line L827 (-202.348, 102.8427) -> (-202.7369, 102.6911)
  line L828 (-202.7369, 102.6911) -> (-203.1188, 102.4932)
  line L829 (-203.1188, 102.4932) -> (-203.802, 101.9877)
  line L830 (-203.802, 101.9877) -> (-204.1032, 101.6804)
  line L831 (-204.1032, 101.6804) -> (-204.3837, 101.325)
  line L832 (-204.3837, 101.325) -> (-204.9032, 100.4363)
  line L833 (-204.9032, 100.4363) -> (-205.1418, 99.9026)
  line L834 (-205.1418, 99.9026) -> (-206.3404, 96.9104)
  line L835 (-206.3404, 96.9104) -> (-206.5621, 96.3891)
  line L836 (-206.5621, 96.3891) -> (-206.7638, 95.9434)
  line L837 (-206.7638, 95.9434) -> (-206.9525, 95.5959)
  line L838 (-206.9525, 95.5959) -> (-207.1353, 95.3763)
  line L839 (-207.1353, 95.3763) -> (-207.3302, 95.2313)
  line L840 (-207.3302, 95.2313) -> (-207.5549, 95.1485)
  line L841 (-207.5549, 95.1485) -> (-207.8525, 95.1096)
  line L842 (-207.8525, 95.1096) -> (-208.258, 95.0966)
  line L843 (-208.258, 95.0966) -> (-213.4755, 95.0966)
  line L844 (-213.4755, 95.0966) -> (-213.3635, 93.956)
  line L845 (-213.3635, 93.956) -> (-213.1799, 92.9872)
  line L846 (-213.1799, 92.9872) -> (-213.0549, 92.561)
  line L847 (-213.0549, 92.561) -> (-212.7033, 91.7998)
  line L848 (-212.7033, 91.7998) -> (-212.4768, 91.4651)
  line L849 (-212.4768, 91.4651) -> (-212.1628, 91.1177)
  line L850 (-212.1628, 91.1177) -> (-211.3769, 90.5618)
  line L851 (-211.3769, 90.5618) -> (-210.38, 90.1913)
  line L852 (-210.38, 90.1913) -> (-209.1724, 90.0062)
  line L853 (-209.1724, 90.0062) -> (-208.4897, 89.983)
  line L854 (-208.4897, 89.983) -> (-207.3414, 90.0341)
  line L855 (-207.3414, 90.0341) -> (-205.9119, 90.3028)
  line L856 (-205.9119, 90.3028) -> (-205.1543, 90.6099)
  line L857 (-205.1543, 90.6099) -> (-204.8342, 90.8019)
  line L858 (-204.8342, 90.8019) -> (-204.5545, 91.0088)
  line L859 (-204.5545, 91.0088) -> (-204.0431, 91.5137)
  line L860 (-204.0431, 91.5137) -> (-203.396, 92.4986)
  line L861 (-203.396, 92.4986) -> (-203.0444, 93.3068)
  line L862 (-203.0444, 93.3068) -> (-201.6382, 96.9383)
  line L863 (-201.6382, 96.9383) -> (-201.4643, 97.3568)
  line L864 (-201.4643, 97.3568) -> (-201.3027, 97.6933)
  line L865 (-201.3027, 97.6933) -> (-201.1509, 97.9441)
  line L866 (-201.1509, 97.9441) -> (-200.999, 98.1129)
  line L867 (-200.999, 98.1129) -> (-200.8182, 98.2157)
  line L868 (-200.8182, 98.2157) -> (-200.5876, 98.2686)
  line L869 (-200.5876, 98.2686) -> (-200.2491, 98.2867)
  line L870 (-200.2491, 98.2867) -> (-199.7446, 98.2926)
  line L871 (-199.7446, 98.2926) -> (-195.7056, 98.2926)
  line L872 (-195.7056, 98.2926) -> (-195.7056, 103.2265)
  line L873 (-195.7056, 103.2265) -> (-198.2865, 103.2265)
  line L874 (-199.6927, 97.218) -> (-199.6927, 89.983)
  line L875 (-199.6927, 89.983) -> (-195.7056, 89.983)
  line L876 (-195.7056, 89.983) -> (-195.7056, 97.218)